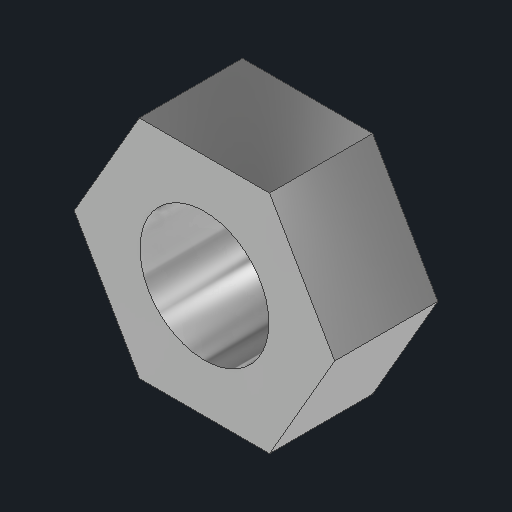
# Autodesk Inventor part: nut_M4
Saved by Autodesk Inventor 2027.1 (Build 311270010, 270A)
## iProperties
Created: 2026-11-09
Part Number: nut_M4
Material: Generic
Description: Hex nut M4 ISO 4032 (7 AF, 3.2 thick)
Document SubType Name: Modeling
Designer: alexg
Density: 1 g/cm^3
Appearance: Stainless Steel - Bright
Author: alexg
Autodesk Inventor part; units mm, degrees
ref_plane "YZ Plane" through (0, 0, 0) normal (1, 0, 0) x (0, 1, 0)
ref_plane "XZ Plane" through (0, 0, 0) normal (0, 1, 0) x (-1, 0, 0)
ref_plane "XY Plane" through (0, 0, 0) normal (0, 0, 1) x (1, 0, 0)
sketch "Hex sketch" plane through (0, 0, 0) normal (0, 0, 1) x (1, 0, 0)
  line L0 (4.0415, 0) -> (2.0207, 3.5)
  line L1 (2.0207, 3.5) -> (-2.0207, 3.5)
  line L2 (-2.0207, 3.5) -> (-4.0415, 0)
  line L3 (-4.0415, 0) -> (-2.0207, -3.5)
  line L4 (-2.0207, -3.5) -> (2.0207, -3.5)
  line L5 (2.0207, -3.5) -> (4.0415, 0)
  constraints: 12 end point
extrude "Hex" add sketch "Hex sketch" along normal blind 3.2
sketch "Thread bore sketch" plane through (0, 0, 0) normal (0, 0, 1) x (1, 0, 0)
  circle A0 centre (0, 0) radius 2
  constraints: 1 centre point
extrude "Thread bore" cut sketch "Thread bore sketch" along normal blind 3.2
body "Solid1"
